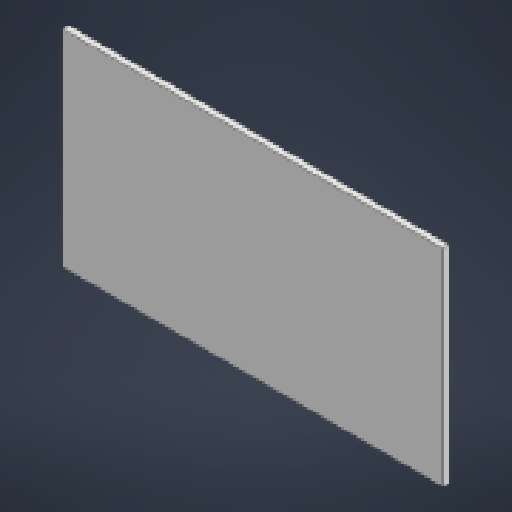
# Autodesk Inventor part: baseabajo
Saved by Autodesk Inventor 2027.1 (Build 311270010, 270A)
## iProperties
Created: 2026-10-12
Part Number: baseabajo
Material: Generic
Document SubType Name: Modeling
Designer: MineS
Density: 1 g/cm^3
Appearance: Default
Author: MineS
Autodesk Inventor part; units mm, degrees
ref_plane "YZ Plane" through (0, 0, 0) normal (1, 0, 0) x (0, 1, 0)
ref_plane "XZ Plane" through (0, 0, 0) normal (0, 1, 0) x (-1, 0, 0)
ref_plane "XY Plane" through (0, 0, 0) normal (0, 0, 1) x (1, 0, 0)
sketch "Sketch1" plane through (0, 0, 0) normal (0, 0, 1) x (1, 0, 0)
  line L0 (3.125, 3.125) -> (3.125, 0) projected
  line L1 (3.125, 0) -> (179.408, 0) projected
  line L2 (179.408, 0) -> (179.408, 3.125) projected
  line L3 (3.125, 3.125) -> (179.408, 3.125) projected
  line L4 (179.408, 96.25) -> (179.408, 0) projected
  line L5 (179.408, 0) -> (182.533, 0) projected
  line L6 (182.533, 96.25) -> (182.533, 0) projected
  line L7 (179.408, 96.25) -> (182.533, 96.25) projected
  line L8 (0, 96.25) -> (0, 0) projected
  line L9 (0, 0) -> (3.125, 0) projected
  line L10 (3.125, 96.25) -> (3.125, 0) projected
  line L11 (0, 96.25) -> (3.125, 96.25) projected
  line L12 (3.125, 96.25) -> (3.125, 93.125) projected
  line L13 (3.125, 93.125) -> (179.408, 93.125) projected
  line L14 (179.408, 93.125) -> (179.408, 96.25) projected
  line L15 (3.125, 96.25) -> (179.408, 96.25) projected
  line L16 (182.533, 0) -> (0, 0)
  line L17 (0, 0) -> (0, 96.25)
  line L18 (0, 96.25) -> (182.533, 96.25)
  line L19 (182.533, 96.25) -> (182.533, 0)
  line L20 (185.533, -3) -> (-3, -3)
  line L21 (-3, -3) -> (-3, 99.25)
  line L22 (-3, 99.25) -> (185.533, 99.25)
  line L23 (185.533, 99.25) -> (185.533, -3)
  dimension "d0" = 3
  constraints: 16 end point, 4 parallel, 2 perpendicular, 1 horizontal, 3 other
  measures "d0" distance between parallel lines of L23 L19
extrude "Extrusion1" add sketch "Sketch1" along normal blind 3.125 contours L3 L2 L1 L0 | L10 L13 L4 L3 | L0 L9 L8 L11 L10 | L4 L7 L6 L5 L2 | L10 L15 L4 L13 | L20 L21 L22 L23
body "Solid1"
